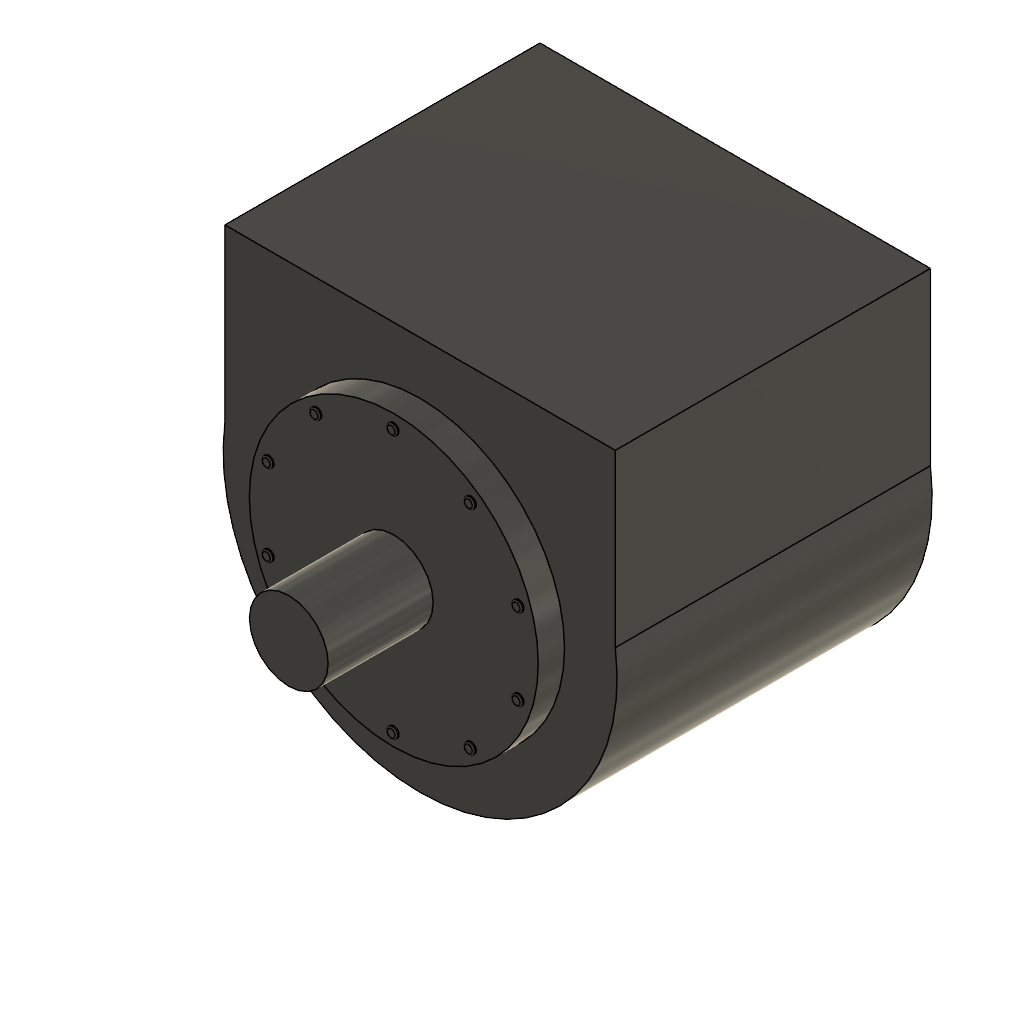
moteur_roue_desherbeur (Autodesk Fusion 360 design; units mm, degrees)
part number: 2026-11-26-21-24-28-065
Autodesk Fusion 360 part; units mm, degrees
note: some values were not read from the file. Set by a fixed rule: which face or edge a step refers to.
sketch "Esquisse1" plane through (0, 0, 0) normal (0, 1, 0) x (1, 0, 0)
  circle A0 centre (0, 0) radius 7.5
  dimension "d1" = 15
  constraint coincident A0.centre origin
  measures "d1" diameter of A0
extrude "Extrusion1" add sketch "Esquisse1" along normal mid plane 12
sketch "Esquisse3" plane through (0, -6, 0) normal (0, -1, 0) x (1, 0, 0)
  circle A0 centre (0, 0) radius 7.5
  circle A1 centre (0, 0) radius 5.5
  dimension "d4" = -2
extrude "Extrusion2" add sketch "Esquisse3" along normal blind 1 contours A1
sketch "Esquisse4" plane through (0, -7, 0) normal (0, -1, 0) x (1, 0, 0)
  circle A0 centre (0, 0) radius 5.5
  circle A1 centre (0, 11) radius 1
  dimension "d7" = 2
  measures "d7" diameter of A1
ref_plane "Plan de construction2" through (0, -0.1327, 7.5) normal (0, 0, 1) x (-1, 0, 0)
sketch "Esquisse7" plane through (0, 0, 7.5) normal (0, 0, 1) x (1, 0, 0)
  line L0 (7.4338, -6) -> (-7.4338, -6)
  line L1 (-7.4338, -6) -> (-7.4338, 6)
  line L2 (-7.4338, 6) -> (7.4338, 6)
  line L3 (7.4338, 6) -> (7.4338, -6)
  line L4 (7.4338, -6) -> (-7.4338, 6) construction
  line L5 (-7.4338, -6) -> (7.4338, 6) construction
  constraint horizontal L0
  constraint perpendicular L0 L1
  constraint parallel L0 L2
  constraint parallel L1 L3
  constraint coincident L4 origin
  constraint coincident L5 origin
extrude "Extrusion6" add sketch "Esquisse7" along normal up to surface end surface at (7.4907, 4, 0.3738)
sketch "Esquisse8" plane through (0, -7, 0) normal (0, -1, 0) x (1, 0, 0)
  circle A0 centre (0, 0) radius 5.5
  circle A1 centre (0, 5) radius 0.2
  dimension "d25" = 0.4
  measures "d25" diameter of A1
extrude "Extrusion7" add sketch "Esquisse8" along normal blind 0.1 contours A1
fillet "Congé2" radius 0.05 1 edges at (-0.1865, -7.1, 4.9277)
pattern_circular "Réseau C2" count 10 over 360 about axis through (0, -7, 0) along (0, -1, 0) of "Extrusion7", "Congé2"
sketch "Esquisse9" plane through (0, -7, 0) normal (0, -1, 0) x (1, 0, 0)
  circle A0 centre (0, 0) radius 5.5
  circle A1 centre (0, 5) radius 0.2
  circle A2 centre (-2.9389, 4.0451) radius 0.2
  circle A3 centre (-4.7553, 1.5451) radius 0.2
  circle A4 centre (-4.7553, -1.5451) radius 0.2
  circle A5 centre (-2.9389, -4.0451) radius 0.2
  circle A6 centre (0, -5) radius 0.2
  circle A7 centre (2.9389, -4.0451) radius 0.2
  circle A8 centre (4.7553, -1.5451) radius 0.2
  circle A9 centre (4.7553, 1.5451) radius 0.2
  circle A10 centre (2.9389, 4.0451) radius 0.2
  circle A11 centre (0, 0) radius 1.5
  constraint coincident A0.centre A11.centre
extrude "Extrusion8" add sketch "Esquisse9" along normal blind 4 contours A11
